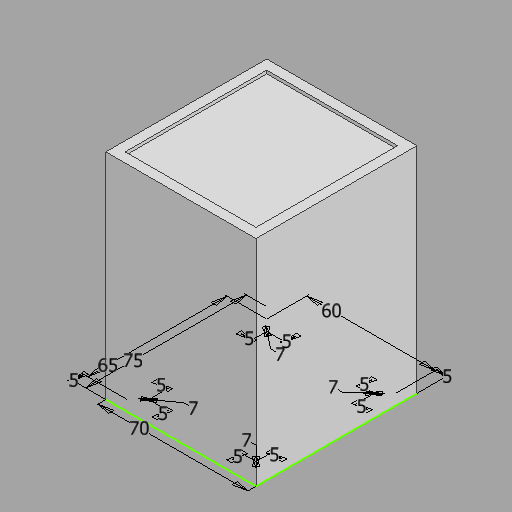
# Autodesk Inventor part: 2차Z(2)
Saved by Autodesk Inventor 2027 (Build 310192000, 192)
## iProperties
Created: 2026-09-16
Part Number: 2차Z(2)
Material: Generic
Document SubType Name: Modeling
Designer: jyjhm
Density: 1 g/cm^3
Appearance: Default
Author: jyjhm
Autodesk Inventor part; units mm, degrees
ref_plane "YZ Plane" through (0, 0, 0) normal (1, 0, 0) x (0, 1, 0)
ref_plane "XZ Plane" through (0, 0, 0) normal (0, 1, 0) x (-1, 0, 0)
ref_plane "XY Plane" through (0, 0, 0) normal (0, 0, 1) x (1, 0, 0)
sketch "Sketch1" plane through (0, 0, 0) normal (0, 1, 0) x (-1, 0, 0)
  line L0 (36.6667, 36.6667) -> (-33.3333, 36.6667)
  line L1 (-33.3333, 36.6667) -> (-33.3333, -38.3333)
  line L2 (-33.3333, -38.3333) -> (36.6667, -38.3333)
  line L3 (36.6667, -38.3333) -> (36.6667, 36.6667)
  line L4 (31.6667, 31.6667) -> (-28.3333, 31.6667)
  line L5 (-28.3333, 31.6667) -> (-28.3333, -33.3333)
  line L6 (-28.3333, -33.3333) -> (31.6667, -33.3333)
  line L7 (31.6667, -33.3333) -> (31.6667, 31.6667)
  circle A0 centre (26.6667, 26.6667) radius 3.5
  circle A1 centre (26.6667, -28.3333) radius 3.5
  circle A2 centre (-23.3333, -28.3333) radius 3.5
  circle A3 centre (-23.3333, 26.6667) radius 3.5
  point P0 (0, 0)
  dimension "d0" = 70
  dimension "d1" = 75
  dimension "d2" = 65
  dimension "d3" = 5
  dimension "d4" = 60
  dimension "d5" = 5
  dimension "d6" = 5
  dimension "d7" = 5
  dimension "d8" = 5
  dimension "d9" = 5
  dimension "d10" = 5
  dimension "d11" = 5
  dimension "d12" = 5
  dimension "d13" = 5
  dimension "d27" = 7
  dimension "d28" = 7
  dimension "d29" = 7
  dimension "d30" = 7
  constraints: 16 end point, 4 centre point, 4 parallel, 2 horizontal, 2 perpendicular
  measures "d0" distance of L0.start L0.end
  measures "d1" distance of L2.end L0.start
  measures "d2" distance of L6.end L4.start
  measures "d3" distance between parallel lines of L0 L4
  measures "d4" distance of L5.end L6.end
  measures "d5" distance between parallel lines of L1 L5
  measures "d6" distance from line of L7 A0.centre
  measures "d7" distance from line of L4 A0.centre
  measures "d8" distance from line of L5 A3.centre
  measures "d9" distance from line of L4 A3.centre
  measures "d10" distance from line of L6 A2.centre
  measures "d11" distance from line of L5 A2.centre
  measures "d12" distance from line of L6 A1.centre
  measures "d13" distance from line of L7 A1.centre
  measures "d27" diameter of A3
  measures "d28" diameter of A0
  measures "d29" diameter of A2
  measures "d30" diameter of A1
extrude "Extrusion1" add sketch "Sketch1" along normal blind 10 contours L3 L2 L1 L0 | L7 L6 L5 L4 | A0 | A1 | A2 | A3
extrude "Extrusion2" add sketch "Sketch1" along normal blind 100 contours L3 L2 L1 L0 | L7 L6 L5 L4 | A0 | A1 | A2 | A3
extrude "Extrusion4" cut sketch "Sketch1" along normal blind 5 contours A0 | A1 | A2 | A3
sketch "Sketch7" plane through (0, 100, 0) normal (0, 1, 0) x (1, 0, 0)
  circle A0 centre (-26.6667, 28.3333) radius 3.5 projected
  circle A1 centre (23.3333, 28.3333) radius 3.5 projected
  circle A2 centre (-26.6667, -26.6667) radius 3.5 projected
  circle A3 centre (23.3333, -26.6667) radius 3.5 projected
  line L0 (33.3333, -36.6667) -> (33.3333, 38.3333) projected
  line L1 (-36.6667, -36.6667) -> (33.3333, -36.6667) projected
  line L2 (-36.6667, 38.3333) -> (-36.6667, -36.6667) projected
  line L3 (33.3333, 38.3333) -> (-36.6667, 38.3333) projected
  line L4 (28.3333, -31.6667) -> (28.3333, 33.3333) projected
  line L5 (-31.6667, -31.6667) -> (28.3333, -31.6667) projected
  line L6 (28.3333, 33.3333) -> (-31.6667, 33.3333) projected
  line L7 (-31.6667, 33.3333) -> (-31.6667, -31.6667) projected
  line L8 (28.8333, 33.8333) -> (-32.1667, 33.8333)
  line L9 (-32.1667, 33.8333) -> (-32.1667, -32.1667)
  line L10 (-32.1667, -32.1667) -> (28.8333, -32.1667)
  line L11 (28.8333, -32.1667) -> (28.8333, 33.8333)
  point P0 (0, 0)
  dimension "d47" = 61
  dimension "d48" = 66
  dimension "d49" = 0.5
  dimension "d50" = 0.5
  constraints: 8 end point, 2 parallel, 1 horizontal, 1 perpendicular
  measures "d47" distance of L9.end L10.end
  measures "d48" distance of L8.end L9.end
  measures "d49" distance between parallel lines of L11 L4
  measures "d50" distance between parallel lines of L10 L5
extrude "Extrusion6" cut sketch "Sketch7" against normal blind 1.5 contours A0 | A1 | A2 | A3 | L5 L7 L6 L4 | L11 L10 L9 L8
body "Solid1"
